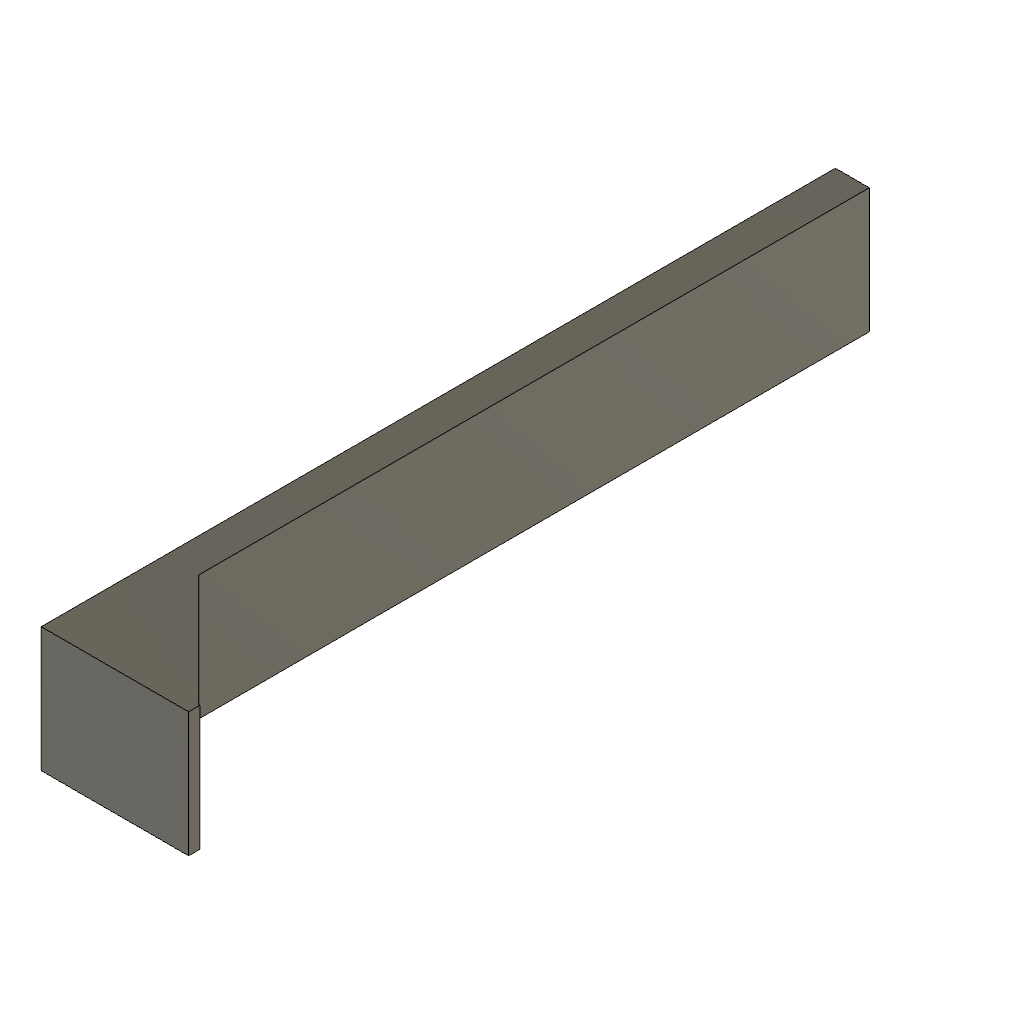
antennatand (Autodesk Fusion 360 design; units mm, degrees)
Autodesk Fusion 360 part; units mm, degrees
sketch "スケッチ1" plane through (0, 0, 0) normal (0, 0, 1) x (1, 0, 0)
  line L0 (1, 0) -> (5, 0)
  line L1 (6, 1) -> (6, 5)
  line L2 (5, 6) -> (1, 6)
  line L3 (0, 5) -> (0, 1)
  arc A0 (1, 6) -> (0, 5) centre (1, 5) ccw
  arc A1 (6, 5) -> (5, 6) centre (5, 5) ccw
  arc A2 (0, 1) -> (1, 0) centre (1, 1) ccw
  arc A3 (5, 0) -> (6, 1) centre (5, 1) ccw
  point P0 (6, 0)
  point P1 (0, 6)
  dimension "d1" = 6
  dimension "d2" = 6
  dimension "d3" = 1
  dimension "d4" = 1
  dimension "d5" = 1
  dimension "d6" = 1
  constraint horizontal L0
  constraint vertical L1
  constraint horizontal L2
  constraint vertical L3
  constraint coincident P1 L2
  constraint coincident P1 L3
  constraint tangent L2 A0
  constraint tangent L3 A0
  constraint tangent L2 A1
  constraint tangent L1 A1
  constraint coincident origin L3
  constraint coincident origin L0
  constraint tangent L3 A2
  constraint tangent L0 A2
  constraint coincident P0 L0
  constraint coincident P0 L1
  constraint tangent L0 A3
  constraint tangent L1 A3
  measures "d1" distance of origin P0
  measures "d2" distance of origin P1
  measures "d3" radius of A0
  measures "d4" radius of A1
  measures "d5" radius of A2
  measures "d6" radius of A3
extrude "押し出し1" add sketch "スケッチ1" along normal blind 3.5 makes body 1
sketch "スケッチ2" plane through (0, 0, 0) normal (0, 0, 1) x (1, 0, 0)
  line L0 (0, 0) -> (3, 0)
  line L1 (3, 10.9) -> (3, 70)
  line L2 (3, 70) -> (0, 70)
  line L3 (0, 70) -> (0, 0)
  line L4 (3, 0) -> (13, 0)
  line L5 (13, 0) -> (13, 1)
  line L6 (13, 1) -> (12.9, 1)
  line L7 (3, 1) -> (3, 0)
  line L8 (12.9, 1) -> (3, 10.9)
  dimension "d9" = 3
  dimension "d10" = 70
  dimension "d11" = 10
  dimension "d12" = 1
  dimension "d13" = 9.9
  dimension "d14" = 9.9
  constraint horizontal L0
  constraint vertical L1
  constraint horizontal L2
  constraint vertical L3
  constraint coincident L0.start L3.end
  constraint horizontal L4
  constraint vertical L5
  constraint horizontal L6
  constraint vertical L7
  constraint coincident L7.start L6
  constraint coincident L1 L7.start
  measures "d9" distance of L0.start L0.end
  measures "d10" distance of L0.start L2.end
  measures "d11" distance of L0.end L4.end
  measures "d12" distance of L0.end L7.start
  measures "d13" distance of L7.start L6.end
  measures "d14" distance of L7.start L1.start
extrude "押し出し2" add sketch "スケッチ2" along normal blind 11 separate body makes body 2
hidden bodies 1
equation "d14 = d13"
